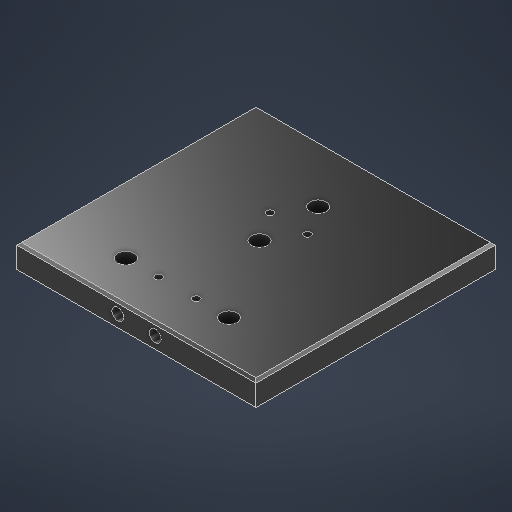
# Autodesk Inventor part: Base plate
Saved by Autodesk Inventor 2026.3 (Build 303398000, 398)
## iProperties
Created: 2026-11-01
Part Number: Base plate
Material: Aluminum 6061
Document SubType Name: Modeling
Designer: ADMIN
Density: 2.7 g/cm^3
Appearance: Glossy - Black
Author: ADMIN
Autodesk Inventor part; units mm, degrees
ref_plane "YZ Plane" through (0, 0, 0) normal (1, 0, 0) x (0, 1, 0)
ref_plane "XZ Plane" through (0, 0, 0) normal (0, 1, 0) x (-1, 0, 0)
ref_plane "XY Plane" through (0, 0, 0) normal (0, 0, 1) x (1, 0, 0)
sketch "Sketch1" plane through (0, 0, 0) normal (0, 1, 0) x (-1, 0, 0)
  line L0 (102, 0) -> (0, 0)
  line L1 (0, 0) -> (0, -102)
  line L2 (0, -102) -> (102, -102)
  line L3 (102, -102) -> (102, 0)
  dimension "d1" = 102
  dimension "d2" = 102
  constraints: 8 end point, 2 parallel, 1 coincident, 1 horizontal, 1 perpendicular
  measures "d1" distance of L1.end L2.end
  measures "d2" distance of L0.end L1.end
extrude "Extrusion1" add sketch "Sketch1" along normal mid plane 10
chamfer "Chamfer1" distance 1 angle 45 4 edges at (-51, 5, 0) (0, 5, -51) (-51, 5, -102) (-102, 5, -51)
sketch "Sketch2" plane through (0, 5, 0) normal (0, 1, 0) x (1, 0, 0)
  line L0 (0, 102) -> (-102, 102) projected
  line L1 (-51, 102) -> (-51, 0) construction
  line L2 (0, 0) -> (-102, 0) projected
  point P0 (-51, 77.5)
  point P1 (-51, 52.5)
  point P2 (-73, 17.5)
  point P3 (-29, 17.5)
  dimension "d8" = 24.5
  dimension "d9" = 25
  dimension "d10" = 35
  dimension "d11" = 44
  constraints: 2 end point, 2 midpoint, 2 vertical alignment, 1 horizontal alignment, 1 symmetric about line
  measures "d8" distance from line of L0 point (-51, 77.5)
  measures "d9" distance of point (-51, 52.5) point (-51, 77.5)
  measures "d10" vertical distance of point (-73, 17.5) point (-51, 52.5)
  measures "d11" diameter of point (-73, 17.5) L1
hole "Hole1" at (-73, 5, -17.5) at (-29, 5, -17.5) at (-51, 5, -77.5) at (-51, 5, -52.5) direction (0, -1, 0) diameter 4 end through all counterbore diameter 7 counterbore depth 5
sketch "Sketch3" plane through (0, 5, 0) normal (0, 1, 0) x (1, 0, 0)
  line L0 (0, 102) -> (-102, 102) projected
  line L1 (-51, 102) -> (-51, 0) construction
  line L2 (0, 0) -> (-102, 0) projected
  point P0 (-43, 65)
  point P1 (-59, 65)
  point P2 (-43, 17.5)
  point P3 (-59, 17.5)
  dimension "d19" = 37
  dimension "d20" = 47.5
  dimension "d21" = 16
  constraints: 2 end point, 2 horizontal alignment, 2 midpoint, 2 symmetric about line, 2 vertical alignment
  measures "d19" distance from line of L0 point (-43, 65)
  measures "d20" distance of point (-43, 17.5) point (-43, 65)
  measures "d21" distance of point (-43, 65) point (-59, 65)
hole "Hole2" at (-43, 5, -65) at (-59, 5, -65) at (-43, 5, -17.5) at (-59, 5, -17.5) direction (0, -1, 0) diameter 3 depth 8
sketch "Sketch4" plane through (-102, -5, 0) normal (0, 0, 1) x (1, 0, 0)
  line L0 (102, 0) -> (0, 0) projected
  line L1 (51, 0) -> (51, 10) construction
  line L2 (47.5, 10) -> (54.5, 10) projected
  point P0 (102, 5)
  point P1 (43, 5)
  point P2 (59, 5)
  dimension "d29" = 5
  dimension "d30" = 16
  constraints: 2 end point, 2 midpoint, 1 horizontal alignment, 1 symmetric about line
  measures "d29" distance from line of L0 point (59, 5)
  measures "d30" distance of point (43, 5) point (59, 5)
hole "Hole3" at (-59, 0, 0) at (-43, 0, 0) direction (0, 0, -1) diameter 3 depth 67.5 counterbore diameter 5 counterbore depth 9.5
body "Solid1"
